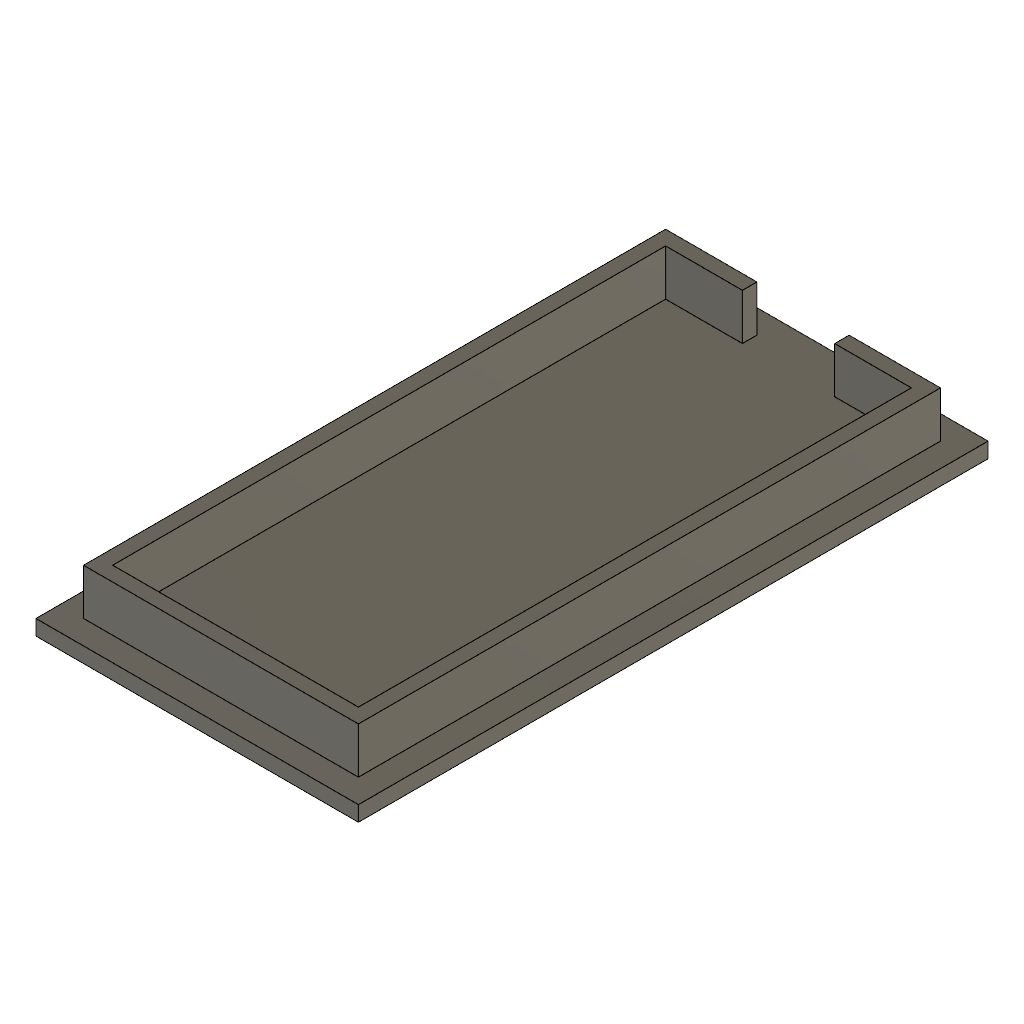
Boost converter cover (Autodesk Fusion 360 design; units mm, degrees)
Autodesk Fusion 360 part; units mm, degrees
sketch "Sketch1" plane through (0, 0, 0) normal (0, 0, 1) x (1, 0, 0)
  line L0 (0, 0) -> (20, 0)
  line L1 (20, 0) -> (20, 40)
  line L2 (20, 40) -> (0, 40)
  line L3 (0, 40) -> (0, 0)
  dimension "d1" = 20
  dimension "d2" = 40
  constraint horizontal L0
  constraint vertical L1
  constraint horizontal L2
  constraint vertical L3
  constraint coincident L0.start L3.end
  measures "d1" distance of L0.start L0.end
  measures "d2" distance of L0.start L2.end
extrude "Extrude1" add sketch "Sketch1" along normal blind 1
sketch "Sketch2" plane through (0, 0, 1) normal (0, 0, 1) x (-1, 0, 0)
  line L0 (0, -40) -> (0, 0)
  line L1 (0, 0) -> (-20, 0)
  line L2 (-20, 0) -> (-20, -40)
  line L3 (-20, -40) -> (0, -40)
  line L4 (-10, 0) -> (-10, -40)
  line L5 (0, -20) -> (-20, -20)
  line L6 (-18.5, -1.5) -> (-1.5, -1.5)
  line L7 (-1.5, -1.5) -> (-1.5, -38.5)
  line L8 (-1.5, -38.5) -> (-18.5, -38.5)
  line L9 (-18.5, -38.5) -> (-18.5, -1.5)
  line L10 (-18.5, -1.5) -> (-1.5, -38.5) construction
  line L11 (-1.5, -1.5) -> (-18.5, -38.5) construction
  point P0 (-10, -20)
  dimension "d5" = 17
  dimension "d6" = 37
  constraint midpoint L1 L4.start
  constraint midpoint L3 L4.end
  constraint midpoint L0 L5.start
  constraint midpoint L2 L5.end
  constraint horizontal L6
  constraint perpendicular L6 L7
  constraint parallel L6 L8
  constraint parallel L7 L9
  constraint coincident L10 P0
  constraint coincident L11 P0
  constraint midpoint L4 P0
  measures "d5" distance of L7.end L8.end
  measures "d6" distance of L6.end L7.end
sketch "Sketch3" plane through (0, 0, 1) normal (0, 0, 1) x (-1, 0, 0)
extrude "Extrude2" add sketch "Sketch2" along normal blind 3 contours L4 L5 L7 L8 | L4 L5 L6 L7 | L4 L5 L8 L9 | L4 L5 L6 L9
sketch "Sketch4" plane through (0, 0, 4) normal (0, 0, 1) x (-1, 0, 0)
  line L0 (-18.5, -38.5) -> (-1.5, -38.5)
  line L1 (-1.5, -38.5) -> (-1.5, -1.5)
  line L2 (-1.5, -1.5) -> (-18.5, -1.5)
  line L3 (-18.5, -1.5) -> (-18.5, -38.5)
  line L4 (-17.5, -2.5) -> (-2.5, -2.5)
  line L5 (-2.5, -2.5) -> (-2.5, -37.5)
  line L6 (-2.5, -37.5) -> (-17.5, -37.5)
  line L7 (-17.5, -37.5) -> (-17.5, -2.5)
  line L8 (-17.5, -2.5) -> (-2.5, -37.5) construction
  line L9 (-2.5, -2.5) -> (-17.5, -37.5) construction
  point P0 (-10, -20)
  dimension "d9" = 15
  dimension "d10" = 35
  constraint horizontal L4
  constraint perpendicular L4 L5
  constraint parallel L4 L6
  constraint parallel L5 L7
  constraint coincident L8 P0
  constraint coincident L9 P0
  measures "d9" distance of L5.end L6.end
  measures "d10" distance of L4.end L5.end
extrude "Extrude3" cut sketch "Sketch4" against normal blind 3 contours L4 L5 L6 L7
sketch "Sketch5" plane through (0, 38.5, 0) normal (0, 1, 0) x (-1, 0, 0)
  line L0 (-18.5, 1) -> (-1.5, 1)
  line L1 (-1.5, 1) -> (-1.5, 4)
  line L2 (-1.5, 4) -> (-18.5, 4)
  line L3 (-18.5, 4) -> (-18.5, 1)
  line L4 (-1.5, 1) -> (-7, 1)
  line L5 (-18.5, 1) -> (-13, 1)
  line L6 (-7, 1) -> (-13, 1)
  line L7 (-13, 1) -> (-13, 4)
  line L8 (-13, 4) -> (-7, 4)
  line L9 (-7, 4) -> (-7, 1)
  dimension "d13" = 5.5
  constraint coincident L0.end L1.start
  constraint coincident L0 L4.end
  constraint coincident L0.start L3.end
  constraint perpendicular L3 L5
  constraint horizontal L6
  constraint vertical L7
  constraint horizontal L8
  constraint vertical L9
  constraint coincident L2 L7.end
  measures "d13" distance of L0.start L5.end
extrude "Extrude4" cut sketch "Sketch5" against normal blind 1 contours L0 L2 L6 L7 L8 L9
extrude "Extrude5" cut 1 faces at (18.5, 26.1667, 2) along direction (-1, 0, 0) blind 0.05
extrude "Extrude6" cut 1 faces at (1.5, 13.8333, 3) along direction (1, 0, 0) blind 0.05
extrude "Extrude7" cut 1 faces at (12.8167, 1.5, 2) along direction (0, 1, 0) blind 0.05
extrude "Extrude8" cut 2 faces at (5.1833, 38.5, 3) (14.8167, 38.5, 2) along direction (0, -1, 0) blind 0.05
extrude "Extrude9" add 1 faces at (12.8167, 1.55, 2) along direction (0, -1, 0) blind 0.5
extrude "Extrude10" add 2 faces at (14.8167, 38.45, 2) (5.1833, 38.45, 3) along direction (0, 1, 0) blind 0.5
extrude "Extrude11" add 1 faces at (1.55, 13.6833, 3) along direction (-1, 0, 0) blind 0.5
extrude "Extrude12" add 1 faces at (18.45, 13.6833, 3) along direction (1, 0, 0) blind 0.5
extrude "Extrude13" add 1 faces at (20, 13.3333, 0.6667) along direction (1, 0, 0) blind 0.5
extrude "Extrude14" add 1 faces at (0, 26.6667, 0.6667) along direction (-1, 0, 0) blind 0.5
extrude "Extrude15" add 1 faces at (6.5, 0, 0.6667) along direction (0, -1, 0) blind 0.5
extrude "Extrude16" add 1 faces at (6.5, 40, 0.6667) along direction (0, 1, 0) blind 0.5
extrude "Extrude17" cut 2 faces at (5.5, 37.5, 3) (14.5, 37.5, 2) along direction (0, 1, 0) blind 0.5
extrude "Extrude18" cut 1 faces at (2.5, 14.3333, 3) along direction (-1, 0, 0) blind 0.5
extrude "Extrude19" cut 1 faces at (17.5, 26.1667, 3) along direction (1, 0, 0) blind 0.5
extrude "Extrude20" cut 1 faces at (7.3333, 2.5, 2) along direction (0, -1, 0) blind 0.5
